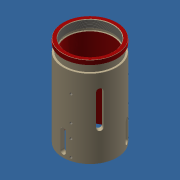
# Autodesk Inventor part: 15-0012-0331
Saved by Autodesk Inventor 2016 SP2 (Build 200236200, 236)
## iProperties
Category: IOP
Company: Universiteit van Amsterdam
RuleStatus: InUse
BeforeDocSave0: Open Form
Created: 2017-10-18
Part Number: 15-0012-0331
Material: Plastic (PEEK)
Document SubType Name: Modeling
Designer: Hans Ellermeijer
Density: 1.32 g/cm^3
Appearance: Beige
Project: Quantum Gas Microscope
Cost Center: 15-0012
User Status: CNC
Authority: Georgios Siviloglou
Mass: 93.0332 g
Surface Area: 376.468 cm^2
Volume: 70.4797 cm^3
Description: Behuizing Lenzen
Author: Hans Ellermeijer
Title: Quantum Gas Microscope
Revision Number: A.1
Autodesk Inventor part; units mm, degrees
ref_plane "XY Plane" through (0, 0, 0) normal (0, 0, 1) x (1, 0, 0)
sketch "Sketch1" plane through (0, 0, 0) normal (0, 0, 1) x (1, 0, 0)
  line L0 (0, 49) -> (0, -49) construction
  line L1 (-49, 0) -> (49, 0) construction
  circle A0 centre (0, 0) radius 35
  circle A1 centre (0, 0) radius 25.4
  dimension "d0" = 70
  dimension "d3" = 50.8
  constraints: 2 centre point, 2 coincident
  measures "d0" diameter of A0
  measures "d3" diameter of A1
sketch "Sketch2" plane through (0, 0, 0) normal (0, 1, 0) x (-1, 0, 0)
  line L0 (30, 103.69) -> (30, 3.5768)
  line L1 (30, 3.5768) -> (25, 0.69)
  line L2 (25, 0.69) -> (9, 0.69)
  line L3 (9, 0.69) -> (9, 4.19)
  line L4 (9, 4.19) -> (8.5, 4.19)
  line L5 (25.4, 5.69) -> (25.4, 103.69)
  line L6 (0, -53.618) -> (0, 129.908) projected
  line L7 (8.5, 4.19) -> (8.5, 4.69)
  line L8 (8.5, 4.69) -> (8.5, 4.69)
  line L9 (25.4, 5.69) -> (8.5, 5.69)
  line L10 (8.5, 5.69) -> (8.5, 4.69)
  line L11 (30, 103.69) -> (25.4, 103.69)
  line L12 (-49, 0) -> (49, 0) construction
  circle A0 centre (0, -10.3) radius 17.1 construction
  line L13 (24.25, 94.69) -> (26.25, 94.69)
  line L14 (26.25, 94.69) -> (26.25, 92.69)
  line L15 (26.25, 92.69) -> (24.25, 92.69)
  line L16 (24.25, 92.69) -> (24.25, 94.69)
  line L17 (25.4, 103.69) -> (25.65, 103.69)
  line L18 (25.65, 103.69) -> (25.65, 94.69)
  line L19 (25.65, 94.69) -> (25.4, 94.69)
  line L20 (25.4, 94.69) -> (25.4, 103.69)
  line L21 (8.5, 4.5406) -> (9, 4.2429)
  line L22 (8.75, 4.3917) -> (0, -10.3) construction
  line L23 (9, 4.2429) -> (9.0768, 4.1971)
  arc A1 (9.1289, 3.9915) -> (9.0768, 4.1971) centre (9, 4.0683) ccw
  line L24 (9.1289, 3.9915) -> (9, 3.7751)
  line L25 (32, 98.69) -> (28, 98.69)
  line L26 (28, 98.69) -> (28, 90.69)
  line L27 (28, 90.69) -> (32, 90.69)
  line L28 (32, 90.69) -> (32, 98.69)
  point P0 (0, 0)
  dimension "d4" = 18
  dimension "d5" = 60
  dimension "d6" = 50.8
  dimension "d7" = 3.5
  dimension "d8" = 17
  dimension "d9" = 0.5
  dimension "d10" = 50
  dimension "d15" = 60
  dimension "d16" = 1
  dimension "d17" = 17
  dimension "d20" = 103.69
  dimension "d23" = 103
  dimension "d24" = 0.69
  dimension "d28" = 34.2
  dimension "d29" = 15.99
  dimension "d30" = 52.5
  dimension "d31" = 2
  dimension "d32" = 9
  dimension "d33" = 2
  dimension "d34" = 51.3
  dimension "d42" = 0.15
  dimension "d43" = 0
  dimension "d45" = 56
  dimension "d46" = 4
  dimension "d47" = 5
  dimension "d48" = 8
  constraints: 54 end point, 11 perpendicular, 7 parallel, 5 point on line, 4 horizontal, 3 tangent, 2 centre point, 2 point on circle, 2 vertical, 1 collinear, 1 midpoint
  measures "d4" diameter of L3 L6
  measures "d5" diameter of L0 L6
  measures "d6" diameter of L5 L6
  measures "d7" distance of L2.end L3.end
  measures "d8" diameter of L7 L6
  measures "d9" distance of L4.end L7.end
  measures "d10" diameter of L1.end L6
  measures "d15" angle of L1 L0
  measures "d16" distance of L9.end L8.end
  measures "d17" diameter of L10 L6
  measures "d20" distance between parallel lines of L12 L11
  measures "d23" distance between parallel lines of L2 L11
  measures "d24" distance between parallel lines of L12 L2
  measures "d28" diameter of A0
  measures "d29" distance from line of L22.end L9
  measures "d30" diameter of L14 L6
  measures "d31" distance of L15.end L13.start
  measures "d32" distance between parallel lines of L11 L13
  measures "d33" distance of L13.start L13.end
  measures "d34" diameter of L18 L6
  measures "d42" radius of A1
  measures "d43" distance from line of L3 A1.centre
  measures "d45" diameter of L26 L6
  measures "d46" distance of L26.end L27.end
  measures "d47" distance between parallel lines of L25 L11
  measures "d48" distance of L27.end L25.start
revolve "Revolution1" add sketch "Sketch2" angle 360 about axis through (0, 0, 0) along (0, 0, 1) contours L0 L25 L26 L27 L1 L2 L3 L24 A1 L23 L21 L7 L10 L9 L5 L15 L14 L13 L18 L11 | L0 L27 L26 L25 | L18 L13 L5 L11 | L13 L14 L15 L5 | L3 L4 L7 L21 L23 A1 L24
fillet "Fillet1" [suppressed]
chamfer "Chamfer1" distance 0.5 angle 45 1 edges at (8.5, 0, 5.69)
revolve "Revolution2" cut sketch "Sketch2" angle 360 about axis through (0, 0, 0) along (0, 0, 1) contours L18 L13 L5 L11 | L13 L14 L15 L5 | L5 L15 L16 L13
chamfer "Chamfer2" distance 0.5 angle 45 3 edges at (25.65, 0, 103.69) (25.65, 0, 94.69) (25.4, 0, 92.69)
thread "Thread1" size "M4x0.7" class "6H" standard "ISO Metric profile" full length
revolve "Revolution3" cut sketch "Sketch2" angle 360 about axis through (0, 0, 0) along (0, 0, 1) contours L3 L4 L7 L21 L23 A1 L24
revolve "Revolution4" cut sketch "Sketch2" angle 360 about axis through (0, 0, 0) along (0, 0, 1) contours L25 L28 L27 L0 | L0 L27 L26 L25
chamfer "Chamfer3" distance 0.2 angle 45 2 edges at (30, 0, 98.69) (30, 0, 90.69)
sketch "Sketch3" plane through (0, 0, 0.69) normal (0, 0, -1) x (-1, 0, 0)
  line L0 (0, -49) -> (0, 49) construction
  line L1 (-49, 0) -> (49, 0) construction
  circle A0 centre (0, 0) radius 35
  circle A1 centre (0, 0) radius 25.4
  dimension "d53" = 70
  dimension "d56" = 50.8
  constraints: 2 centre point, 2 coincident
  measures "d53" diameter of A0
  measures "d56" diameter of A1
extrude "Extrusion2" cut sketch "Sketch3" against normal blind 3 contours A0 | A1
extrude "Extrusion3" cut sketch "Sketch3" against normal blind 5 contours A1
sketch "Sketch4" plane through (0, 0, 3.69) normal (0, 0, -1) x (-1, 0, 0)
  line L0 (0, -49) -> (0, 49) construction
  line L1 (-49, 0) -> (49, 0) construction
  point P0 (0, 0)
  point P1 (27.5, 0)
  dimension "d59" = 27.5
  constraints: 1 point on line
  measures "d59" distance from line of L0 point (27.5, 0)
hole "Hole1" at (-27.5, 0, 3.69) direction (0, 0, 1) diameter 2.459 depth 12 tip angle 118 thread size "M3x0.5" class "6H" standard "ISO Metric profile"
pattern_circular "Circular Pattern1" count 6 over 360 about axis through (0, 0, 54.69) along (0, 0, -1) of "Hole1"
sketch "Sketch5" plane through (0, 0, 0) normal (0, 1, 0) x (-1, 0, 0)
  line L0 (0, -20.738) -> (0, 124.428) construction
  line L1 (-49, 0) -> (49, 0) construction
  line L2 (0, 9.69) -> (0, 29.69) construction
  line L3 (3, 9.69) -> (3, 29.69)
  line L4 (-3, 29.69) -> (-3, 9.69)
  arc A0 (-3, 9.69) -> (3, 9.69) centre (0, 9.69) ccw
  arc A1 (3, 29.69) -> (-3, 29.69) centre (0, 29.69) ccw
  line L5 (25.4, 3.69) -> (-25.4, 3.69) projected
  line L6 (0, 72.69) -> (0, 37.69) construction
  line L7 (-3, 72.69) -> (-3, 37.69)
  line L8 (3, 37.69) -> (3, 72.69)
  arc A2 (3, 72.69) -> (-3, 72.69) centre (0, 72.69) ccw
  arc A3 (-3, 37.69) -> (3, 37.69) centre (0, 37.69) ccw
  point P0 (0, 0)
  point P1 (0, 19.69)
  point P2 (0, 55.19)
  dimension "d70" = 6
  dimension "d71" = 6
  dimension "d72" = 20
  dimension "d75" = 6
  dimension "d76" = 35
  dimension "d79" = 8
  constraints: 16 end point, 8 point on circle, 8 tangent, 4 centre point, 4 point on line, 2 midpoint, 2 parallel
  measures "d70" diameter of A1
  measures "d71" distance from line of L2.start L5
  measures "d72" distance of L4.start L4.end
  measures "d75" diameter of A3
  measures "d76" distance of L7.start L7.end
  measures "d79" distance of L2.end L6.end
extrude "Extrusion4" cut sketch "Sketch5" against normal blind 41.75 contours A0 L4 A1 L3
extrude "Extrusion5" cut sketch "Sketch5" along normal blind 41.75 contours A2 L8 A3 L7
pattern_circular "Circular Pattern2" count 3 over 360 about axis through (0, 0, -10) along (0, 0, 1) of "Extrusion4", "Extrusion5"
chamfer "Chamfer4" distance 0.25 angle 45 1 edges at (30, 0, 103.69)
ref_plane "Work Plane1" through (0, 0, 0) normal (0.9659, 0.2588, 0) x (0, 0, 1)
sketch "Sketch6" plane through (0, 0, 0) normal (0.9659, 0.2588, 0) x (0, 0, 1)
  line L0 (90.49, 30) -> (3.69, 30) projected
  point P0 (0, 0)
ref_plane "Work Plane2" through (7.7646, -28.9778, 90.49) normal (0.2588, -0.9659, 0) x (0, 0, -1)
sketch "Sketch7" plane through (7.7646, -28.9778, 90.49) normal (0.2588, -0.9659, 0) x (0, 0, -1)
  line L0 (90.49, -60.0125) -> (90.49, 60.0125) construction
  line L1 (111.228, 0) -> (-33.938, 0) construction
  line L2 (86.8, 30) -> (86.8, -30) construction
  point P0 (90.49, 0)
  point P1 (83.3, 0)
  point P2 (65.3, 0)
  point P3 (50.3, 0)
  point P4 (22.3, 0)
  dimension "d88" = 3.5
  dimension "d89" = 21.5
  dimension "d90" = 36.5
  dimension "d91" = 64.5
  constraints: 4 point on line
  measures "d88" distance from line of L2 point (83.3, 0)
  measures "d89" distance from line of L2 point (65.3, 0)
  measures "d90" distance from line of L2 point (50.3, 0)
  measures "d91" distance from line of L2 point (22.3, 0)
hole "Hole2" at (7.7646, -28.9778, 7.19) at (7.7646, -28.9778, 25.19) at (7.7646, -28.9778, 40.19) at (7.7646, -28.9778, 68.19) direction (-0.2588, 0.9659, 0) diameter 2.459 depth 8 tip angle 118 thread size "M3x0.5" class "6H" standard "ISO Metric profile"
pattern_circular "Circular Pattern3" count 3 over 360 about axis through (0, 0, -10) along (0, 0, 1) of "Hole2"
ref_plane "Work Plane5" through (0, 0, 0) normal (-0.866, -0.5, 0) x (0, 0, 1)
equation "\"d56\" = d6"
body "Solid2"
